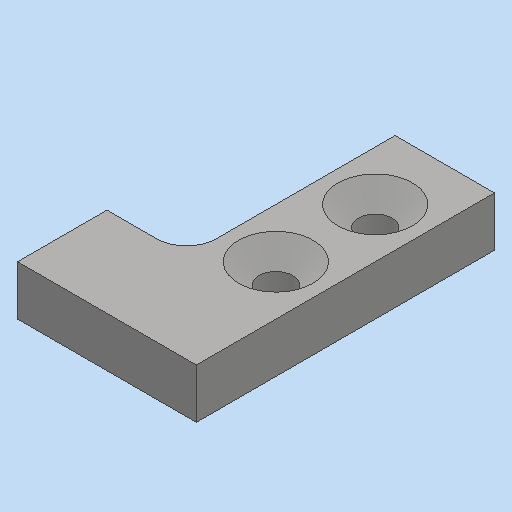
# Autodesk Inventor part: MM0948AN100_G01_113
Saved by Autodesk Inventor 2023.3 (Build 273359000, 359)
## iProperties
Part Number: MM0948AN100_G01_113
Material: 1.2343 X38CrMoV5-1
Description: =<RBPARTNOTITLE2>
Document SubType Name: Modeling
Designer: ric7an
Mass: 13.4701 g
Surface Area: 12.7721 cm^2
Volume: 1.71593 cm^3
Density: 7.85 g/cm^3
Appearance: Stahl - normal AnP
Created: 2023-03-23
RBDOCUMENTTYPE: DRF
RBDOCUMENTVERSION: 00
RBDRAWINGMAINSCALE: 1:1
RBDRAWINGMISSINGSPEC: --
RBDRAWINGVOLUME: --
RBGBEDGESIN1: +0,5
RBGBEDGESIN2: +0,2
RBGBEDGESOUT1: -0,3
RBGBEDGESOUT2: -0,1
RBMATERIAL: =<Material>
RBMATMEETS: --
RBMATNO: =<Part Number>
RBPARTMADEOF: 5 x 30 x 18 (FM)
RBPARTNO: SIEHE MNR
RBPARTNOTITLE1: manufactured part
RBPARTNOTITLE2: Anfertigungsteil
RBPARTSAFETYINDICATOR: --
RBSURFACE: plasma nitrided 1000 HV, Nht 0,1 + 0,1
RBSURFACE2: plasmanitriert 1000 HV, Nht 0,1 + 0,1
RBZEDGESNORM: ISO13715:2002-06
RBZGENDIMCLASS: m
RBZGENDIMNORM: ISO 2768-1:1989-11
RBZGENGEOCLASS: H
RBZGENGEONORM: ISO 2768-2:1989-11
RBZSURFACENORM: ISO13D2:2002-02
RBZTOLERANCENORM: ISO 14405-1:2010-12
AnP_Material: =<Material>
AnP_TemplVers: 20190222
AnP_Kategorie: 1
MaxAbmaße: 5 x 30 x 18 (FM)
AnP_Kommentar_aktuell: =<Comments>
AnP_Material_aktuell: =<Material>
Author: FH/Wi
Keywords: =<RBPARTMADEOF>
Comments: =<RBSURFACE2>
Revision Number: 01
Autodesk Inventor part; units mm, degrees
ref_plane "YZ Plane" through (0, 0, 0) normal (1, 0, 0) x (0, 1, 0)
ref_plane "XZ Plane" through (0, 0, 0) normal (0, 1, 0) x (-1, 0, 0)
ref_plane "XY Plane" through (0, 0, 0) normal (0, 0, 1) x (1, 0, 0)
sketch "Skizze1" plane through (0, 0, 0) normal (0, 0, 1) x (1, 0, 0)
  line L0 (-5, 15) -> (5, 15)
  line L1 (5, 15) -> (5, -15)
  line L2 (5, -15) -> (-5, -15)
  line L3 (-5, -15) -> (-5, 15)
  line L4 (0, 21) -> (0, -21) projected
  line L5 (-16.6, 0) -> (8.6, 0) projected
  line L6 (-5, -15) -> (-13, -15)
  line L7 (-13, -15) -> (-13, -6)
  line L8 (-13, -6) -> (-5, -6)
  line L9 (-5, -6) -> (-5, -15)
  point P0 (0, 0)
  dimension "d0" = 10
  dimension "d1" = 30
  dimension "d17" = 9
  dimension "d18" = 8
  constraints: 16 end point, 4 parallel, 2 horizontal, 2 perpendicular, 2 other
  measures "d0" distance of L0.start L0.end
  measures "d1" distance of L0.end L1.end
  measures "d17" distance of L6.end L7.end
  measures "d18" distance of L7.end L8.end
extrude "Extrusion1" add sketch "Skizze1" along normal blind 5
sketch "Skizze2" plane through (0, 0, 5) normal (0, 0, 1) x (1, 0, 0)
  line L0 (0, 21) -> (0, -21) projected
  line L1 (-16.6, 0) -> (8.6, 0) projected
  line L2 (-13, -15) -> (5, -15) projected
  point P0 (0, 0)
  point P1 (0, 8)
  point P2 (0, -2)
  point P3 (-5, -15)
  dimension "d4" = 10
  dimension "d14" = 13
  constraints: 2 point on line
  measures "d4" distance of point (0, -2) point (0, 8)
  measures "d14" distance from line of L2 point (0, -2)
hole "Bohrung1" at (0, 8, 5) at (0, -2, 5) direction (0, 0, -1) diameter 3.4 depth 8 tip angle 118 countersink diameter 7.5 countersink angle 90 clearance for "Innensechskant-Senkkopfschraube ISO 10642" size "M3" standard "ISO"
fillet "Rundung1" radius 3 1 edges at (-5, -6, 2.5)
